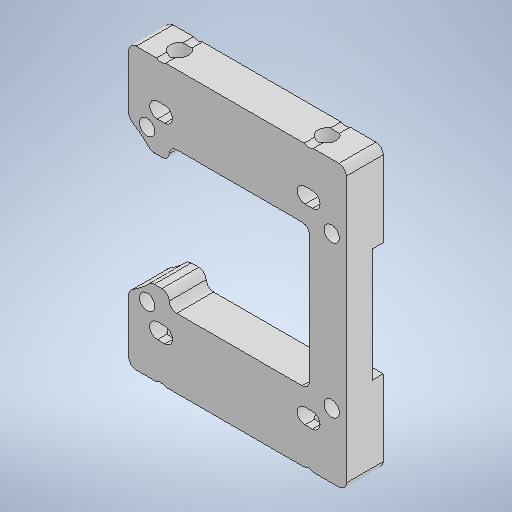
# Autodesk Inventor part: AP5.0_servo-mount2
Saved by Autodesk Inventor 2025.2 (Build 292293000, 293)
## iProperties
Created: 2024-04-22
Part Number: AP5.0_servo-mount2
Material: 一般
Document SubType Name: Sheet Metal
Designer: 8326d
Density: 1 g/cm^3
Sheet Metal Rule: Default_mm
Appearance: 既定
Author: 8326d
## iProperties of the stored document T3.0_servo-mount_3D プリント.ipt
Created: 2024-09-23
Part Number: T3.0_servo-mount_3D プリント
Material: 一般
Document SubType Name: Modeling
Designer: 8326d
Density: 1 g/cm^3
Appearance: 既定
Author: 8326d
Autodesk Inventor part; units mm, degrees
ref_plane "YZ Plane" through (0, 0, 0) normal (1, 0, 0) x (0, 1, 0)
ref_plane "XZ Plane" through (0, 0, 0) normal (0, 1, 0) x (-1, 0, 0)
ref_plane "XY Plane" through (0, 0, 0) normal (0, 0, 1) x (1, 0, 0)
sketch "スケッチ1" plane through (0, 0, 0) normal (0, 0, 1) x (1, 0, 0)
  line L0 (-14.75, -19) -> (14.75, -19)
  line L1 (14.75, -19) -> (14.75, 19)
  line L2 (14.75, 19) -> (-14.75, 19)
  line L3 (-14.75, 19) -> (-14.75, -19)
  line L4 (-14.75, -19) -> (14.75, 19) construction
  line L5 (14.75, -19) -> (-14.75, 19) construction
  point P0 (0, 0)
  dimension "d0" = 29.5
  dimension "d1" = 38
  measures "d0" distance of L1.end L2.end
  measures "d1" distance of L0.end L1.end
extrude "プレート1" add sketch "スケッチ1" along normal blind 5
sketch "スケッチ2" plane through (0, 0, 5) normal (0, 0, 1) x (1, 0, 0)
  line L0 (-12.25, -10.25) -> (12.75, -10.25) construction
  line L1 (12.75, -10.25) -> (12.75, 10.25) construction
  line L2 (12.75, 10.25) -> (-12.25, 10.25) construction
  line L3 (-12.25, 10.25) -> (-12.25, -10.25) construction
  line L4 (-12.25, -10.25) -> (12.75, 10.25) construction
  line L5 (12.75, -10.25) -> (-12.25, 10.25) construction
  line L6 (14.75, 19) -> (14.75, -19) construction
  line L7 (-14.75, -19) -> (-14.75, 19) projected
  point P0 (0, 0)
  point P1 (0.25, 0)
  dimension "d3" = 25
  dimension "d4" = 20.5
  dimension "d42" = 2.5
  constraints: 12 end point, 2 midpoint, 2 parallel, 1 horizontal, 1 horizontal alignment, 1 perpendicular
  measures "d3" distance of L2.end L1.end
  measures "d4" distance of L1.end L0.end
  measures "d42" distance between parallel lines of L7 L3
hole "穴1" at (-12.25, 10.25, 5) at (12.75, 10.25, 5) at (12.75, -10.25, 5) at (-12.25, -10.25, 5) direction (0, 0, -1) diameter 2.1 end through all
sketch "スケッチ3" plane through (0, 0, 0) normal (0, 0, -1) x (-1, 0, 0)
  line L0 (-14.75, -19) -> (-14.75, 19) projected
  line L1 (14.75, 19) -> (14.75, -19) projected
  line L2 (-14.75, 7.7) -> (14.75, 7.7)
  line L3 (14.75, -7.7) -> (-14.75, -7.7)
  line L4 (-14.75, 19) -> (14.75, 19) projected
  line L5 (14.75, -19) -> (-14.75, -19) projected
  point P0 (0, 0)
  dimension "d13" = 11.3
  dimension "d14" = 11.3
  constraints: 4 end point, 4 point on line, 3 perpendicular
  measures "d13" distance between parallel lines of L4 L2
  measures "d14" distance between parallel lines of L5 L3
extrude "押し出し1" cut sketch "スケッチ3" against normal blind 1.5 contours L0 L2 L1 L3
sketch "スケッチ4" plane through (0, 0, 5) normal (0, 0, 1) x (1, 0, 0)
  line L0 (-14.75, 19) -> (14.75, 19) projected
  line L1 (14.75, -19) -> (-14.75, -19) projected
  circle A0 centre (-20.25, 0) radius 11.5
  line L2 (14.75, 19) -> (14.75, -19) projected
  line L3 (9.75, -9.6) -> (-9.25, -9.6)
  line L4 (-9.25, -9.6) -> (-9.25, 9.6)
  line L5 (-9.25, 9.6) -> (9.75, 9.6)
  line L6 (9.75, 9.6) -> (9.75, -9.6)
  line L7 (9.75, -9.6) -> (-9.25, 9.6) construction
  line L8 (-9.25, -9.6) -> (9.75, 9.6) construction
  line L9 (-9.25, 7.7) -> (-11.7083, 7.7)
  line L10 (-11.7083, 7.7) -> (-11.7083, -7.7)
  line L11 (-11.7083, -7.7) -> (-9.25, -7.7)
  line L12 (-9.25, -7.7) -> (-9.25, 7.7)
  point P0 (0, 0)
  point P1 (14.75, 0)
  point P2 (0.25, 0)
  point P3 (-9.25, 0)
  point P4 (-11.7083, 7.7)
  dimension "d18" = 23
  dimension "d17" = 35
  dimension "d22" = 19
  dimension "d41" = 11
  dimension "d73" = 19.2
  dimension "d74" = 2.4583
  constraints: 20 end point, 4 midpoint, 4 parallel, 3 horizontal alignment, 2 horizontal, 2 perpendicular, 1 point on line, 3 other
  measures "d17" distance from line of L2 point (-20.25, 0)
  measures "d22" distance between parallel lines of L6 L12
  measures "d41" distance from line of point (-20.25, 0) L12
  measures "d73" distance between parallel lines of L3 L5
  measures "d74" distance between parallel lines of L4 L10
extrude "押し出し2" cut sketch "スケッチ4" against normal through all
fillet "フィレット1" radius 1 14 edges at (-9.25, 9.6, 2.5) (-9.25, -9.6, 2.5) (9.75, -9.6, 2.5) (9.75, 9.6, 2.5) (-9.25, 7.7, 2.5) (-9.25, -7.7, 2.5) (-11.7083, -7.7, 2.5) (-11.7083, 7.7, 2.5) (-14.75, 10.0995, 2.5) (-14.75, -10.0995, 2.5) (-14.75, -19, 2.5) (14.75, -19, 2.5) (14.75, 19, 2.5) (-14.75, 19, 2.5)
sketch "スケッチ10" plane through (0, 0, 5) normal (0, 0, 1) x (1, 0, 0)
  line L0 (-13.75, 19) -> (13.75, 19) projected
  circle A0 centre (9.635, 19.85) radius 1.05
  circle A1 centre (-10.365, 19.85) radius 1.05
  line L1 (14.75, 18) -> (14.75, -18) projected
  point P0 (0, 0)
  dimension "d75" = 2.1
  dimension "d76" = 2.1
  dimension "d77" = 5.115
  dimension "d78" = 20
  dimension "d79" = 0.85
  dimension "d80" = 0.85
  constraints: 2 centre point
  measures "d75" diameter of A0
  measures "d76" diameter of A1
  measures "d77" distance from line of L1 A0.centre
  measures "d78" distance of A0.centre A1.centre
  measures "d79" distance from line of L0 A0.centre
  measures "d80" distance from line of L0 A1.centre
extrude "押し出し6" cut sketch "スケッチ10" against normal through all
sketch "スケッチ11" plane through (0, 0, 5) normal (0, 0, 1) x (1, 0, 0)
  line L0 (-10.865, 12.95) -> (-9.865, 12.95) construction
  line L1 (-10.865, 11.9) -> (-9.865, 11.9)
  line L2 (-9.865, 14) -> (-10.865, 14)
  arc A0 (-10.865, 14) -> (-10.865, 11.9) centre (-10.865, 12.95) ccw
  arc A1 (-9.865, 11.9) -> (-9.865, 14) centre (-9.865, 12.95) ccw
  line L3 (-10.365, 12.95) -> (-9.365, 12.95) construction
  line L4 (9.135, 12.95) -> (10.135, 12.95) construction
  line L5 (9.135, 11.9) -> (10.135, 11.9)
  line L6 (10.135, 14) -> (9.135, 14)
  arc A2 (9.135, 14) -> (9.135, 11.9) centre (9.135, 12.95) ccw
  arc A3 (10.135, 11.9) -> (10.135, 14) centre (10.135, 12.95) ccw
  line L7 (9.635, 12.95) -> (10.635, 12.95) construction
  arc A4 (-10.9814, 19) -> (-9.7486, 19) centre (-10.365, 19.85) ccw projected
  arc A5 (9.0186, 19) -> (10.2514, 19) centre (9.635, 19.85) ccw projected
  line L8 (-13.75, 19) -> (-10.9814, 19) projected
  point P0 (0, 0)
  dimension "d83" = 0.5
  dimension "d84" = 0
  dimension "d85" = 2.1
  dimension "d86" = 0.5
  dimension "d87" = 0
  dimension "d88" = 2.1
  dimension "d89" = 5
  constraints: 20 end point, 8 point on circle, 8 tangent, 4 centre point, 3 horizontal, 3 parallel, 2 collinear, 2 midpoint, 2 vertical alignment, 1 point on line
  measures "d83" distance of L3.start L0.end
  measures "d84" distance between parallel lines of L0 L3
  measures "d85" diameter of A1
  measures "d86" distance of L7.start L4.end
  measures "d87" distance between parallel lines of L4 L7
  measures "d88" diameter of A3
  measures "d89" distance between parallel lines of L8 L2
extrude "押し出し7" cut sketch "スケッチ11" against normal through all
sketch "スケッチ12" plane through (-9.7486, 19, 0) normal (0, 1, 0) x (1, 0, 0)
  line L0 (-1.2329, -5) -> (-1.2329, 0) projected
  line L1 (0, -5) -> (-1.2329, -5) projected
  line L2 (0, 0) -> (0, -5) projected
  line L3 (-1.2329, 0) -> (0, 0) projected
  line L4 (18.7671, -5) -> (18.7671, 0) projected
  line L5 (20, -5) -> (18.7671, -5) projected
  line L6 (20, 0) -> (20, -5) projected
  line L7 (18.7671, 0) -> (20, 0) projected
  line L8 (19.3836, 0) -> (19.3836, -5) construction
  line L9 (-1.2329, 0) -> (0, 0) construction
  line L10 (-0.6164, 0) -> (-0.6164, -5) construction
  point P0 (9.7486, 0)
  point P1 (19.3836, -2.5)
  point P2 (-0.6164, -2.5)
  point P3 (-0.6164, -2.5)
  constraints: 6 midpoint, 4 end point, 1 coincident
hole "穴4" at (9.635, 19, 2.5) at (-10.365, 19, 2.5) direction (0, -1, 0) diameter 2.5 depth 5 tip angle 118
mirror "ミラー2" about plane through (0, 0, 0) normal (0, 1, 0) of "押し出し6", "押し出し7", "穴4"
equation "\"d11\" = Thickness"
equation "\"d14\" = d13"
equation "\"d80\" = d79"
equation "\"d97\" = Thickness"
equation "\"d2\" = Thickness"
equation "\"BendRadius\" = Thickness"
equation "\"BendReliefWidth\" = Thickness"
equation "\"BendReliefDepth\" = 0.5 * Thickness"
equation "\"TransitionRadius\" = BendRadius"
equation "\"JacobiRadiusSize\" = BendRadius"
equation "\"GapSize\" = Thickness"
equation "\"Thickness\" = 5"
